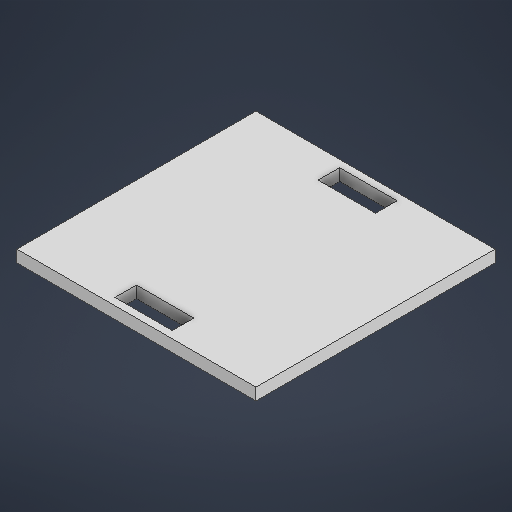
# Autodesk Inventor part: Medio
Saved by Autodesk Inventor 2025.2 (Build 292293000, 293)
## iProperties
Created: 2025-06-04
Part Number: Medio
Material: Genérico
Document SubType Name: Modeling
Designer: Niko
Density: 1 g/cm^3
Appearance: Valor por defecto
Author: Niko
Autodesk Inventor part; units mm, degrees
ref_plane "YZ Plane" through (0, 0, 0) normal (1, 0, 0) x (0, 1, 0)
ref_plane "XZ Plane" through (0, 0, 0) normal (0, 1, 0) x (-1, 0, 0)
ref_plane "XY Plane" through (0, 0, 0) normal (0, 0, 1) x (1, 0, 0)
sketch "Boceto1" plane through (0, 0, 0) normal (0, 1, 0) x (-1, 0, 0)
  line L0 (50, 50) -> (-50, 50)
  line L1 (-50, 50) -> (-50, -50)
  line L2 (-50, -50) -> (50, -50)
  line L3 (50, -50) -> (50, 50)
  line L4 (50, 30) -> (50, 50)
  line L5 (50, 50) -> (50, 45)
  line L6 (12, -40) -> (12, -38)
  line L7 (12, -38) -> (-12, -38)
  line L8 (-12, -38) -> (-12, -47)
  line L9 (-12, -47) -> (12, -47)
  line L10 (12, -47) -> (12, -38)
  line L11 (12, 40) -> (12, 38)
  line L12 (12, 38) -> (-12, 38)
  line L13 (-12, 38) -> (-12, 47)
  line L14 (-12, 47) -> (12, 47)
  line L15 (12, 47) -> (12, 38)
  constraints: 32 end point, 4 parallel, 2 horizontal, 2 perpendicular, 1 point on line
extrude "Extrusión2" add sketch "Boceto1" along normal blind 5
